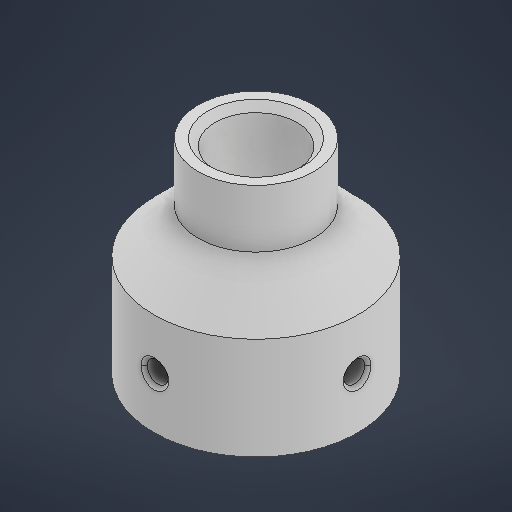
# Autodesk Inventor part: axialLock_mainShaft
Saved by Autodesk Inventor 2027.1 (Build 311270010, 270A)
## iProperties
Created: 2026-10-10
Part Number: axialLock_mainShaft
Material: Generic
Document SubType Name: Modeling
Designer: lucao
Density: 0.517367 g/cm^3
Appearance: Default
Mass: 5.75 g
Surface Area: 50.9328 cm^2
Volume: 11.114 cm^3
Author: lucao
## iProperties of the stored document axialLock_arm_3DPrint.ipt
Created: 2026-10-13
Part Number: axialLock_arm_3DPrint
Material: Generic
Document SubType Name: Modeling
Designer: lucao
Density: 1 g/cm^3
Appearance: Default
Author: lucao
Autodesk Inventor part; units mm, degrees
ref_plane "XZ Plane" through (0, 0, 0) normal (0, 1, 0) x (-1, 0, 0)
ref_plane "XY Plane" through (0, 0, 0) normal (0, 0, 1) x (1, 0, 0)
sketch "Sketch1" plane through (0, 0, 0) normal (1, 0, 0) x (0, 1, 0)
  line L0 (0, 0) -> (24.3365, 0)
  line L1 (30, 6.025) -> (30, 8.5)
  line L2 (30, 8.5) -> (21.5, 8.5)
  line L3 (21.5, 8.5) -> (15, 15)
  line L4 (15, 15) -> (0, 15)
  line L5 (0, 15) -> (0, 6.025)
  line L6 (0, 6.025) -> (30, 6.025)
  point P0 (0, 10.5125)
  dimension "d0" = 12.05
  dimension "d1" = 17
  dimension "d2" = 30
  dimension "d3" = 45
  dimension "d4" = 30
  dimension "d5" = 15
  dimension "d6" = 0
  constraints: 14 end point, 3 perpendicular, 1 horizontal, 1 midpoint, 1 parallel, 1 vertical
  measures "d0" diameter of L6 L0
  measures "d1" diameter of L2 L0
  measures "d2" diameter of L4 L0
  measures "d3" angle of L2 L3
  measures "d4" distance from line of point (0, 10.512) L1
  measures "d5" distance of L3.end L4.end
  measures "d6" distance from line of L0.start L5
revolve "Revolution1" add sketch "Sketch1" angle 360 about axis through (0, 0, 0) along (0, 1, 0)
chamfer "Chamfer1" distance 1 angle 45 2 edges at (0, 0, -6.025) (0, 30, -6.025)
sketch "Sketch2" plane through (0, 0, 0) normal (1, 0, 0) x (0, 1, 0)
  circle A0 centre (7.5, 0) radius 1.55
  line L0 (0, -15) -> (0, 15) projected
  line L1 (15, -15) -> (15, 15) projected
  line L2 (0, -15) -> (15, -15) projected
  point P0 (0, 0)
  point P1 (7.5, -15)
  point P2 (0, 0)
  dimension "d11" = 3.1
  constraints: 2 midpoint, 1 centre point, 1 horizontal alignment, 1 vertical alignment
  measures "d11" diameter of A0
extrude "Extrusion1" cut sketch "Sketch2" along normal through all both and the other way through all
ref_plane "Work Plane1" through (10.5, 0, 0) normal (1, 0, 0) x (0, 1, 0)
sketch "Sketch3" plane through (10.5, 0, 0) normal (1, 0, 0) x (0, 1, 0)
  line L0 (9.0877, -2.75) -> (5.9123, -2.75)
  line L1 (5.9123, -2.75) -> (4.3246, 0)
  line L2 (4.3246, 0) -> (5.9123, 2.75)
  line L3 (5.9123, 2.75) -> (9.0877, 2.75)
  line L4 (9.0877, 2.75) -> (10.6754, 0)
  line L5 (10.6754, 0) -> (9.0877, -2.75)
  line L6 (1, -6.025) -> (1, 6.025) projected
  line L7 (29, 6.025) -> (29, -6.025) projected
  line L8 (0, -15) -> (0, 15) projected
  line L9 (15, -15) -> (15, 15) projected
  line L10 (0, -15) -> (15, -15) projected
  line L11 (0, 15) -> (15, 15) projected
  line L12 (5.9123, -2.75) -> (0, -2.75)
  line L13 (5.9123, 2.75) -> (0, 2.75)
  point P0 (0, 0)
  point P1 (7.5, -1.55)
  point P2 (7.5, 0)
  point P3 (7.5, -1.55)
  point P4 (7.5, -1.55)
  point P5 (7.5, -1.55)
  point P6 (7.5, -1.55)
  point P7 (7.5, -15)
  dimension "d15" = 5.5
  constraints: 16 end point, 2 horizontal alignment, 2 perpendicular, 2 point on line, 1 midpoint, 1 vertical alignment, 19 other
  measures "d15" distance between parallel lines of L3 L0
extrude "Extrusion2" cut sketch "Sketch3" along normal mid plane 3 contours L0 L1 L2 L3 L4 L5 | L12 L6 L13 L2 L1 | L12 L8 L13 L6
chamfer "Chamfer2" distance 0.5 angle 45 4 edges at (12, 0, 0) (10.5, 0, 2.75) (10.5, 0, -2.75) (9, 0, 0)
chamfer "Chamfer3" distance 0.5 angle 45 2 edges at (14.9911, 6.0391, 0.5178) (-14.9911, 6.0391, 0.5178)
pattern_circular "Circular Pattern1" count 4 over 360 about axis through (0, 15, 0) along (0, 1, 0) of "Extrusion1"
pattern_circular "Circular Pattern2" count 4 over 360 about axis through (0, 15, 0) along (0, 1, 0) of "Extrusion2", "Chamfer2"
chamfer "Chamfer4" distance 0.5 angle 45 3 edges at (1.55, 7.5002, 14.9197) (-1.55, 7.4997, 14.9197) (-0.0202, 5.9501, -15)
body "Solid1"
